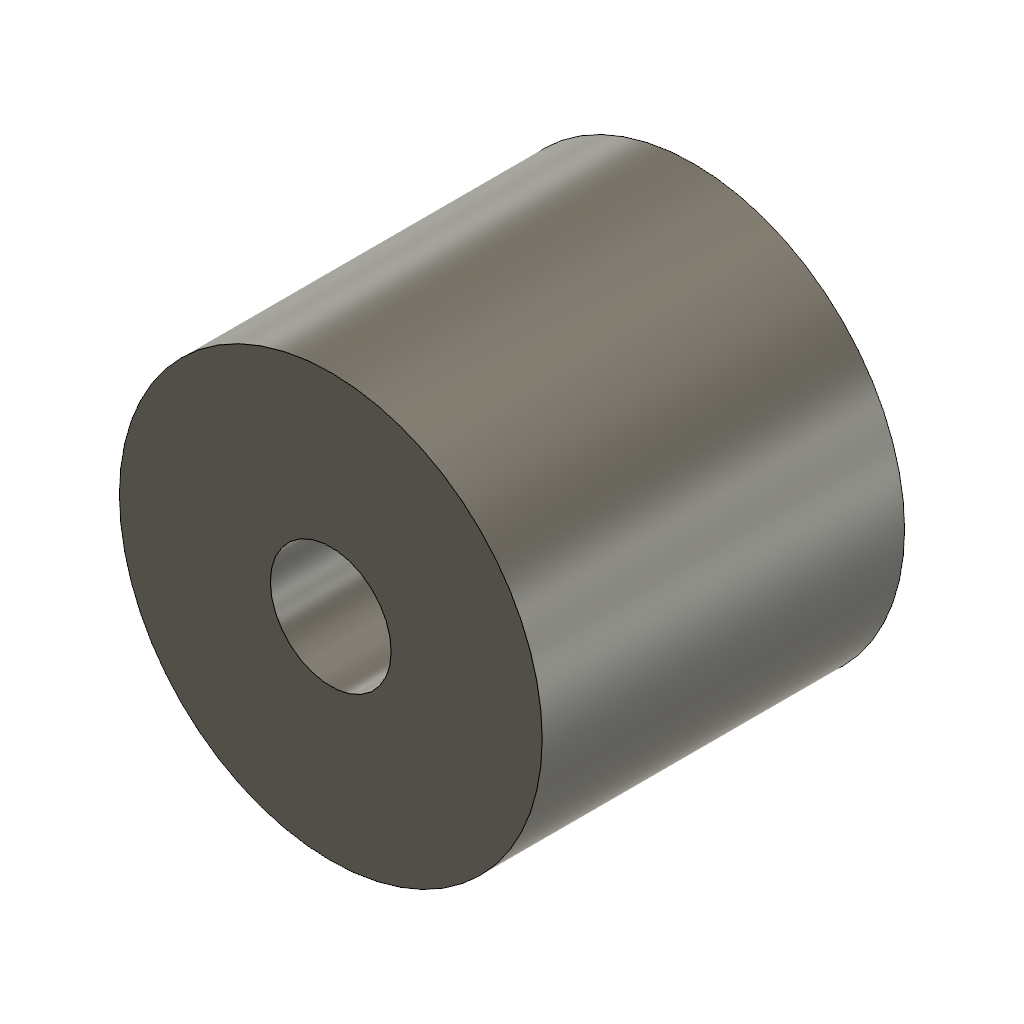
P05-fusion-edit-outer_radius_mm-7 (Autodesk Fusion 360 design; units mm, degrees)
part number: 2026-11-14-20-01-42-974
Autodesk Fusion 360 part; units mm, degrees
sketch "AnnulusProfile" plane through (0, 0, 0) normal (0, 1, 0) x (1, 0, 0)
  line L0 (2, 0) -> (7, 0)
  line L1 (7, 0) -> (7, -12)
  line L2 (7, -12) -> (2, -12)
  line L3 (2, -12) -> (2, 0)
  line L4 (1.75, 0) -> (22.5, 0)
  dimension "inner_radius_mm" = 2
  dimension "outer_radius_mm" = 7
  dimension "height_mm" = 12
  constraint horizontal L0
  constraint vertical L1
  constraint horizontal L2
  constraint vertical L3
  constraint coincident L0.start L4
  measures "inner_radius_mm" horizontal distance of origin L0.start
  measures "outer_radius_mm" horizontal distance of origin L0.end
  measures "height_mm" vertical distance of L0.start L2.end
revolve "Revolution" add sketch "AnnulusProfile" angle 360 about axis through (0, 0, 1.75) along (0, 0, 1)
equation "angle_deg = 360 deg"
